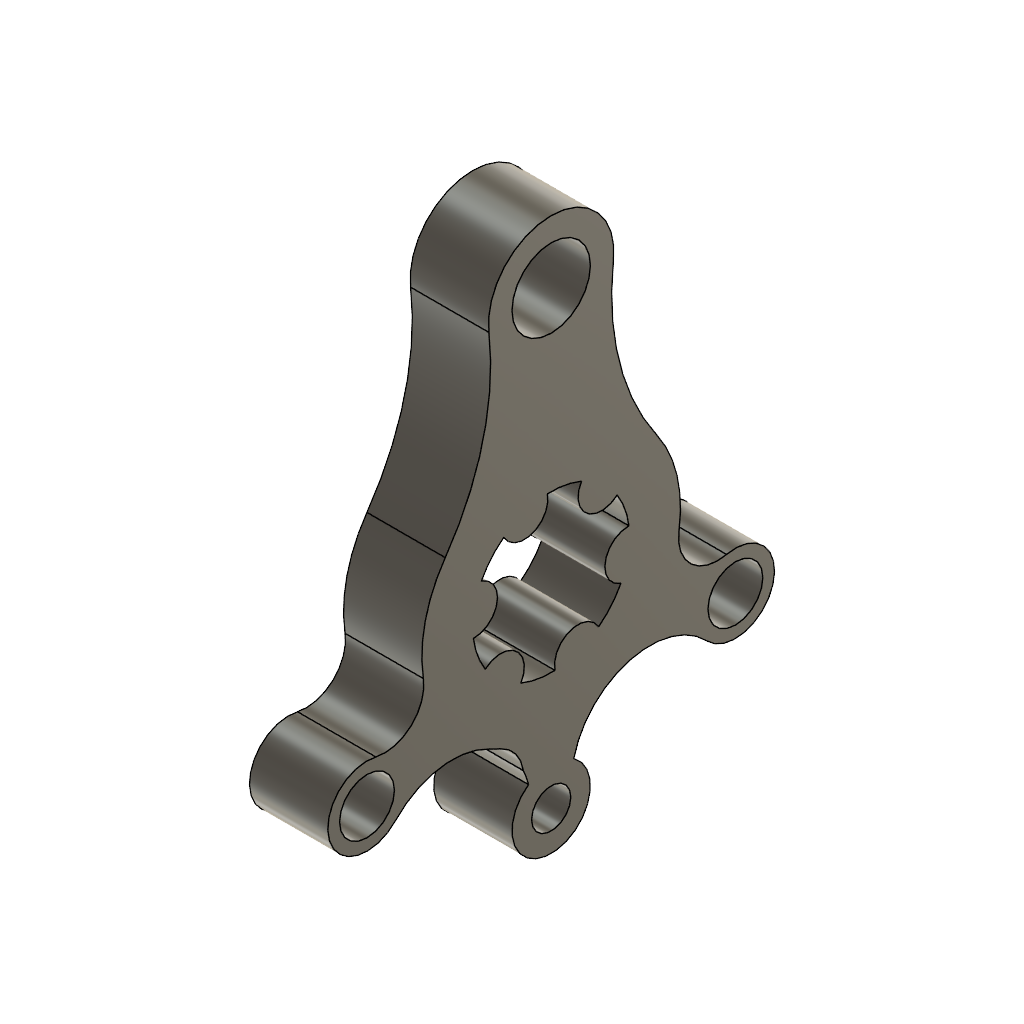
Ex-1.1 (Autodesk Fusion 360 design; units mm, degrees)
Autodesk Fusion 360 part; units mm, degrees
sketch "Sketch1" plane through (0, 0, 0) normal (1, 0, 0) x (0, 1, 0)
  circle A0 centre (0, 65) radius 10
  circle A1 centre (-47, -26) radius 7
  circle A2 centre (0, -50) radius 5
  arc A3 (-27.0298, 18.9312) -> (-15.8903, 63.1292) centre (-79.4513, 55.6462) ccw
  arc A4 (-44.752, -16.2559) -> (-32.6194, -4.9975) centre (-42.5041, -6.5119) ccw
  arc A5 (-5.7884, -41.8456) -> (-39.7367, -32.8734) centre (-25.21, -46.6203) ccw
  arc A6 (-8.5079, -44.745) -> (-14.279, -29.8718) centre (-17.0159, -39.49) ccw
  arc A7 (-27.0298, 18.9312) -> (-32.6194, -4.9975) centre (0, 0) ccw
  arc A8 (-15.6968, -29.0277) -> (-13.0587, -30.3063) centre (0, 0) ccw
  arc A9 (15.8903, 63.1292) -> (-15.8903, 63.1292) centre (0, 65) ccw
  arc A10 (-44.752, -16.2559) -> (-39.7367, -32.8734) centre (-47, -26) ccw
  arc A11 (-5.7884, -41.8456) -> (5.7884, -41.8456) centre (0, -50) ccw
  arc A12 (15.8903, 63.1292) -> (27.0298, 18.9312) centre (79.4513, 55.6462) ccw
  arc A13 (32.6194, -4.9975) -> (27.0298, 18.9312) centre (0, 0) ccw
  arc A14 (32.6194, -4.9975) -> (44.752, -16.2559) centre (42.5041, -6.5119) ccw
  arc A15 (39.7367, -32.8734) -> (44.752, -16.2559) centre (47, -26) ccw
  circle A16 centre (47, -26) radius 7
  arc A17 (39.7367, -32.8734) -> (5.7884, -41.8456) centre (25.21, -46.6203) ccw
  arc A18 (-12.1076, 15.9187) -> (-0.959, 19.977) centre (-6.8411, 18.7936) ccw
  arc A19 (-19.8398, -2.5261) -> (-17.7801, 9.158) centre (-19.6963, 3.4722) ccw
  arc A20 (-7.7323, -18.4448) -> (-16.8211, -10.819) centre (-12.8551, -15.3214) ccw
  arc A21 (12.1076, -15.9187) -> (0.959, -19.977) centre (6.8411, -18.7936) ccw
  arc A22 (19.8398, 2.5261) -> (17.7801, -9.158) centre (19.6963, -3.4722) ccw
  arc A23 (7.7323, 18.4448) -> (16.8211, 10.819) centre (12.8551, 15.3214) ccw
  arc A24 (7.7323, 18.4448) -> (-0.959, 19.977) centre (0, 0) ccw
  arc A25 (19.8398, 2.5261) -> (16.8211, 10.819) centre (0, 0) ccw
  arc A26 (12.1076, -15.9187) -> (17.7801, -9.158) centre (0, 0) ccw
  arc A27 (-12.1076, 15.9187) -> (-17.7801, 9.158) centre (0, 0) ccw
  arc A28 (-19.8398, -2.5261) -> (-16.8211, -10.819) centre (0, 0) ccw
  arc A29 (-7.7323, -18.4448) -> (0.959, -19.977) centre (0, 0) ccw
  dimension "d1" = 65
  dimension "d2" = 20
  dimension "d3" = 32
  dimension "d4" = 40
  dimension "d5" = 66
  dimension "d6" = 10
  dimension "d7" = 20
  dimension "d8" = 20
  dimension "d9" = 14
  dimension "d10" = 26
  dimension "d11" = 24
  dimension "d12" = 47
  dimension "d13" = 128
  dimension "d14" = 20
  dimension "d15" = 40
  dimension "d16" = 20
  dimension "d17" = 12
  dimension "d19" = 360
  constraint concentric A0 A9
  constraint coincident A7.centre A8.centre
  constraint concentric A1 A10
  constraint concentric A2 A11
  constraint tangent A3 A9
  constraint tangent A3 A7
  constraint tangent A4 A10
  constraint tangent A4 A7
  constraint tangent A5 A10
  constraint tangent A5 A8
  constraint tangent A6 A11
  constraint tangent A6 A8
  constraint coincident A5 A6.end
  constraint coincident A6.start A11
  constraint coincident A6 A8.end
  constraint coincident A5 A8.start
  constraint concentric A7 A8
  constraint coincident A18.centre A27
  constraint concentric A24 A27
  constraint concentric A25 A26
  constraint concentric A26 A29
  constraint concentric A27 A28
  constraint concentric A28 A29
  measures "d1" distance of A0.centre A7.centre
  measures "d2" diameter of A0
  measures "d3" diameter of A9
  measures "d4" diameter of A27
  measures "d5" diameter of A7
  measures "d6" diameter of A2
  measures "d7" diameter of A11
  measures "d8" diameter of A10
  measures "d9" diameter of A1
  measures "d10" vertical distance of A7.centre A1.centre
  measures "d11" vertical distance of A1.centre A2.centre
  measures "d12" horizontal distance of A7.centre A1.centre
  measures "d13" diameter of A3
  measures "d14" diameter of A4
  measures "d15" diameter of A5
  measures "d16" diameter of A6
  measures "d17" diameter of A18
extrude "Extrude1" add sketch "Sketch1" against normal blind 20 contours A3 A4 A5 A6 A7 A8 A9 A10 A11 A12 A13 A14 A15 A17
